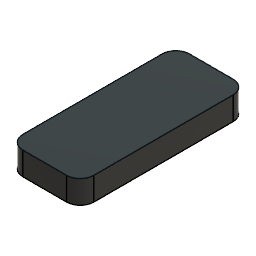
usb_hub_v1 (Autodesk Fusion 360 design; units mm, degrees)
part number: 2026-11-05-11-15-51-954
Autodesk Fusion 360 part; units mm, degrees
sketch "Sketch1" plane through (0, 0, 0) normal (0, 0, 1) x (1, 0, 0)
  line L0 (26, 61) -> (-26, 61)
  line L1 (-26, 61) -> (-26, -61)
  line L2 (-26, -61) -> (26, -61)
  line L3 (26, -61) -> (26, 61)
  line L4 (26, 61) -> (-26, -61) construction
  line L5 (-26, 61) -> (26, -61) construction
  dimension "d1" = 52
  dimension "d2" = 122
  constraint horizontal L0
  constraint perpendicular L0 L1
  constraint parallel L0 L2
  constraint parallel L1 L3
  constraint coincident L4 origin
  constraint coincident L5 origin
  measures "d1" distance of L1.end L2.end
  measures "d2" distance of L0.end L1.end
extrude "Extrude1" add sketch "Sketch1" along normal blind 17
fillet "Fillet1" radius 10 4 edges at (26, -61, 8.5) (26, 61, 8.5) (-26, -61, 8.5) (-26, 61, 8.5)
sketch "Sketch2" plane through (0, 0, 17) normal (0, 0, 1) x (-1, 0, 0)
  arc A0 (16, -61) -> (26, -51) centre (16, -51) ccw
  line L0 (26, -51) -> (26, 51)
  arc A1 (26, 51) -> (16, 61) centre (16, 51) ccw
  line L1 (16, 61) -> (-16, 61)
  arc A2 (-16, 61) -> (-26, 51) centre (-16, 51) ccw
  line L2 (-26, 51) -> (-26, -51)
  arc A3 (-26, -51) -> (-16, -61) centre (-16, -51) ccw
  line L3 (-16, -61) -> (16, -61)
